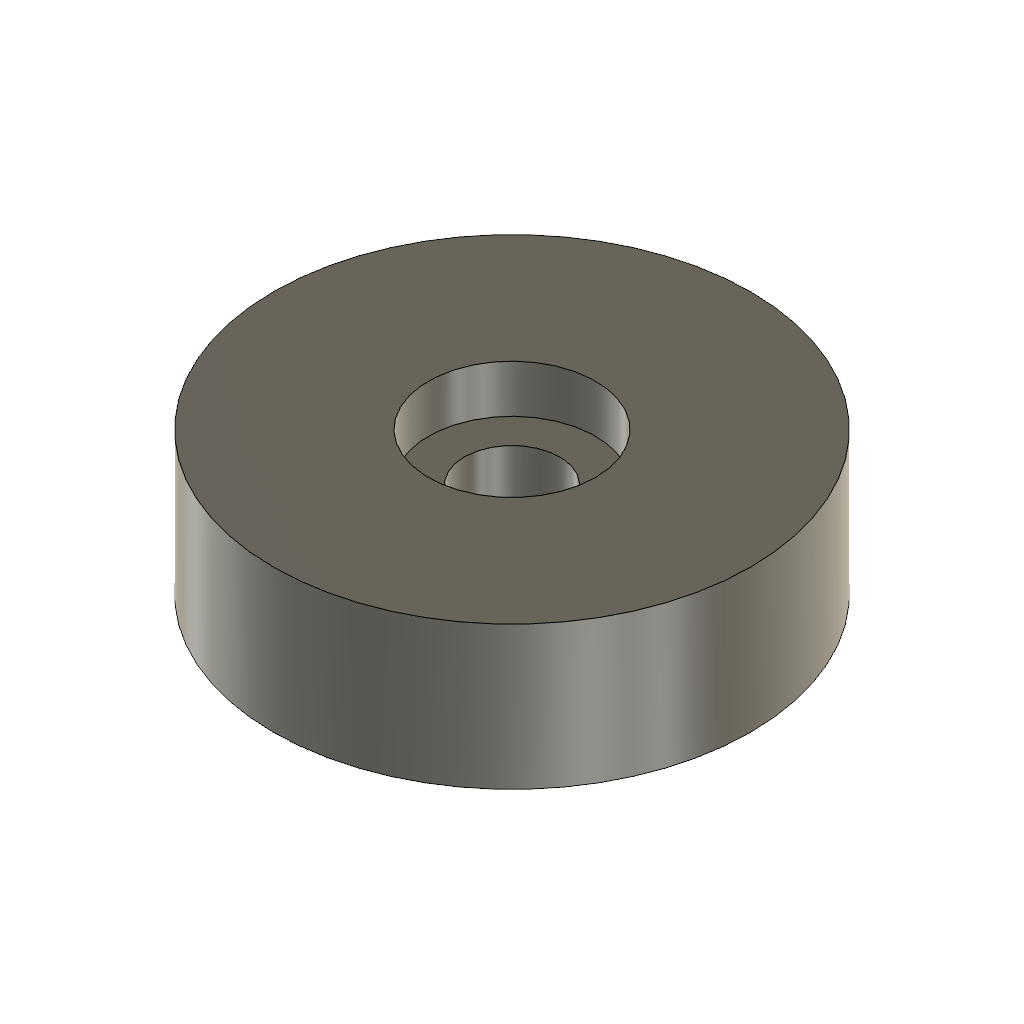
DiscBore (Autodesk Fusion 360 design; units mm, degrees)
part number: 2026-11-12-16-07-09-717
Autodesk Fusion 360 part; units mm, degrees
sketch "Disc sketch" plane through (0, 0, 0) normal (0, 0, 1) x (1, 0, 0)
  circle A0 centre (0, 0) radius 20
extrude "Extrude1" add sketch "Disc sketch" along normal blind 12
sketch "Pocket extrude sketch" plane through (0, 0, 0) normal (0, 0, 1) x (1, 0, 0)
  circle A0 centre (12, 0) radius 3
extrude "Pocket extrude" cut sketch "Pocket extrude sketch" along normal blind 6
pattern_circular "Pocket ring" count 4 over 360 about axis through (0, 0, 1.75) along (0, 0, 1) of "Pocket extrude"
hole "Center bore" at (0, 0, 12) direction (0, 0, -1) diameter 8 end through all counterbore diameter 14 counterbore depth 4
